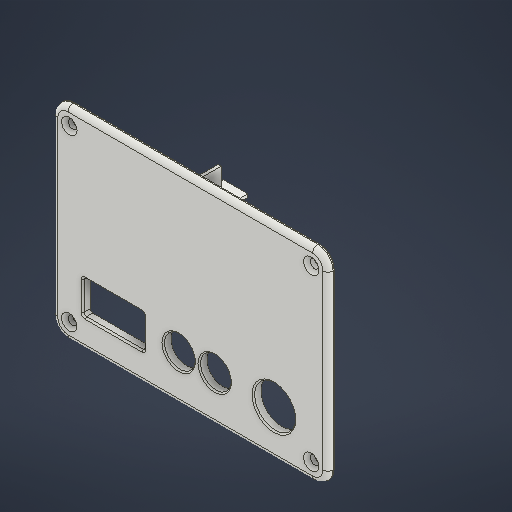
# Autodesk Inventor part: housing_lid
Saved by Autodesk Inventor 2027.1 (Build 311270010, 270A)
## iProperties
Created: 2026-10-22
Part Number: housing_lid
Material: 일반
Document SubType Name: Modeling
Designer: sungjun
Density: 1 g/cm^3
Appearance: housing_lid_c
Author: sungjun
Autodesk Inventor part; units mm, degrees
ref_plane "작업 평면1" through (0, 0, 58) normal (0, 0, 1) x (1, 0, 0)
sketch "스케치1" plane through (0, 0, 58) normal (0, 0, 1) x (1, 0, 0)
  line L0 (0, 0) -> (107, 0)
  line L1 (107, 0) -> (107, 79)
  line L2 (107, 79) -> (0, 79)
  line L3 (0, 79) -> (0, 0)
  constraints: 8 end point, 2 parallel, 1 horizontal, 1 perpendicular
extrude "돌출1" add sketch "스케치1" along normal mid plane 3
fillet "모깎기1" radius 6 4 edges at (0, 0, 58) (0, 79, 58) (107, 79, 58) (107, 0, 58)
fillet "모깎기2" radius 2 8 edges at (105.2426, 1.7574, 59.5) (107, 39.5, 59.5) (105.2426, 77.2426, 59.5) (53.5, 79, 59.5) (1.7574, 77.2426, 59.5) (0, 39.5, 59.5) (1.7574, 1.7574, 59.5) (53.5, 0, 59.5)
chamfer "모따기1" distance 0.6 angle 45 8 edges at (53.5, 79, 56.5) (105.2426, 77.2426, 56.5) (107, 39.5, 56.5) (105.2426, 1.7574, 56.5) (53.5, 0, 56.5) (1.7574, 1.7574, 56.5) (0, 39.5, 56.5) (1.7574, 77.2426, 56.5)
ref_plane "작업 평면2" through (0, 0, 58) normal (0, 0, 1) x (1, 0, 0)
sketch "스케치2" plane through (0, 0, 58) normal (0, 0, 1) x (1, 0, 0)
  circle A0 centre (6.5, 6.5) radius 1.7
  constraints: 1 centre point
extrude "돌출2" cut sketch "스케치2" along normal mid plane 5
ref_plane "작업 평면3" through (0, 0, 58) normal (0, 0, 1) x (1, 0, 0)
sketch "스케치3" plane through (0, 0, 58) normal (0, 0, 1) x (1, 0, 0)
  circle A0 centre (100.5, 6.5) radius 1.7
  constraints: 1 centre point
extrude "돌출3" cut sketch "스케치3" along normal mid plane 5
ref_plane "작업 평면4" through (0, 0, 58) normal (0, 0, 1) x (1, 0, 0)
sketch "스케치4" plane through (0, 0, 58) normal (0, 0, 1) x (1, 0, 0)
  circle A0 centre (6.5, 72.5) radius 1.7
  constraints: 1 centre point
extrude "돌출4" cut sketch "스케치4" along normal mid plane 5
ref_plane "작업 평면5" through (0, 0, 58) normal (0, 0, 1) x (1, 0, 0)
sketch "스케치5" plane through (0, 0, 58) normal (0, 0, 1) x (1, 0, 0)
  circle A0 centre (100.5, 72.5) radius 1.7
  constraints: 1 centre point
extrude "돌출5" cut sketch "스케치5" along normal mid plane 5
chamfer "모따기2" distance 1.3 angle 45 4 edges at (98.8, 72.5, 59.5) (4.8, 72.5, 59.5) (98.8, 6.5, 59.5) (4.8, 6.5, 59.5)
ref_plane "작업 평면6" through (0, 0, 55.5) normal (0, 0, 1) x (1, 0, 0)
sketch "스케치6" plane through (0, 0, 55.5) normal (0, 0, 1) x (1, 0, 0)
  line L0 (3.3, 11) -> (5.3, 11)
  line L1 (5.3, 11) -> (5.3, 68)
  line L2 (5.3, 68) -> (3.3, 68)
  line L3 (3.3, 68) -> (3.3, 11)
  constraints: 8 end point, 2 parallel, 1 horizontal, 1 perpendicular
extrude "돌출6" add sketch "스케치6" along normal mid plane 2
ref_plane "작업 평면7" through (0, 0, 55.5) normal (0, 0, 1) x (1, 0, 0)
sketch "스케치7" plane through (0, 0, 55.5) normal (0, 0, 1) x (1, 0, 0)
  line L0 (101.7, 11) -> (103.7, 11)
  line L1 (103.7, 11) -> (103.7, 68)
  line L2 (103.7, 68) -> (101.7, 68)
  line L3 (101.7, 68) -> (101.7, 11)
  constraints: 8 end point, 2 parallel, 1 horizontal, 1 perpendicular
extrude "돌출7" add sketch "스케치7" along normal mid plane 2
ref_plane "작업 평면8" through (0, 0, 51.6) normal (0, 0, 1) x (1, 0, 0)
sketch "스케치8" plane through (0, 0, 51.6) normal (0, 0, 1) x (1, 0, 0)
  line L0 (51.5, 32.1) -> (52.7, 32.1)
  line L1 (52.7, 32.1) -> (52.7, 75.7)
  line L2 (52.7, 75.7) -> (51.5, 75.7)
  line L3 (51.5, 75.7) -> (51.5, 32.1)
  constraints: 8 end point, 2 parallel, 1 horizontal, 1 perpendicular
extrude "돌출8" add sketch "스케치8" along normal mid plane 9.8
ref_plane "작업 평면9" through (0, 0, 51.6) normal (0, 0, 1) x (1, 0, 0)
sketch "스케치9" plane through (0, 0, 51.6) normal (0, 0, 1) x (1, 0, 0)
  line L0 (24.8, 32.1) -> (52.7, 32.1)
  line L1 (52.7, 32.1) -> (52.7, 33.3)
  line L2 (52.7, 33.3) -> (24.8, 33.3)
  line L3 (24.8, 33.3) -> (24.8, 32.1)
  constraints: 8 end point, 2 parallel, 1 horizontal, 1 perpendicular
extrude "돌출9" add sketch "스케치9" along normal mid plane 9.8
ref_plane "작업 평면10" through (0, 0, 40.55) normal (0, 0, 1) x (1, 0, 0)
sketch "스케치10" plane through (0, 0, 40.55) normal (0, 0, 1) x (1, 0, 0)
  line L0 (3.3, 32.1) -> (15.3, 32.1)
  line L1 (15.3, 32.1) -> (15.3, 33.3)
  line L2 (15.3, 33.3) -> (3.3, 33.3)
  line L3 (3.3, 33.3) -> (3.3, 32.1)
  constraints: 8 end point, 2 parallel, 1 horizontal, 1 perpendicular
extrude "돌출10" add sketch "스케치10" along normal mid plane 31.9
ref_plane "작업 평면11" through (0, 0, 32.45) normal (0, 0, 1) x (1, 0, 0)
sketch "스케치11" plane through (0, 0, 32.45) normal (0, 0, 1) x (1, 0, 0)
  line L0 (15.3, 32.1) -> (24.8, 32.1)
  line L1 (24.8, 32.1) -> (24.8, 33.3)
  line L2 (24.8, 33.3) -> (15.3, 33.3)
  line L3 (15.3, 33.3) -> (15.3, 32.1)
  constraints: 8 end point, 2 parallel, 1 horizontal, 1 perpendicular
extrude "돌출11" add sketch "스케치11" along normal mid plane 48.1
ref_plane "작업 평면12" through (0, 0, 58) normal (0, 0, 1) x (1, 0, 0)
sketch "스케치12" plane through (0, 0, 58) normal (0, 0, 1) x (1, 0, 0)
  line L0 (11.65, 11.15) -> (35.65, 11.15)
  line L1 (35.65, 11.15) -> (35.65, 24.15)
  line L2 (35.65, 24.15) -> (11.65, 24.15)
  line L3 (11.65, 24.15) -> (11.65, 11.15)
  constraints: 8 end point, 2 parallel, 1 horizontal, 1 perpendicular
extrude "돌출12" cut sketch "스케치12" along normal mid plane 5
fillet "모깎기3" radius 1 4 edges at (35.65, 11.15, 58) (35.65, 24.15, 58) (11.65, 24.15, 58) (11.65, 11.15, 58)
chamfer "모따기3" distance 0.6 angle 45 8 edges at (11.9429, 11.4429, 59.5) (23.65, 11.15, 59.5) (11.9429, 23.8571, 59.5) (23.65, 24.15, 59.5) (35.3571, 23.8571, 59.5) (35.65, 17.65, 59.5) (35.3571, 11.4429, 59.5) (11.65, 17.65, 59.5)
ref_plane "작업 평면13" through (0, 0, 58) normal (0, 0, 1) x (1, 0, 0)
sketch "스케치13" plane through (0, 0, 58) normal (0, 0, 1) x (1, 0, 0)
  circle A0 centre (49, 17.65) radius 6
  constraints: 1 centre point
extrude "돌출13" cut sketch "스케치13" along normal mid plane 5
ref_plane "작업 평면14" through (0, 0, 58) normal (0, 0, 1) x (1, 0, 0)
sketch "스케치14" plane through (0, 0, 58) normal (0, 0, 1) x (1, 0, 0)
  circle A0 centre (63, 17.65) radius 6
  constraints: 1 centre point
extrude "돌출14" cut sketch "스케치14" along normal mid plane 5
ref_plane "작업 평면15" through (0, 0, 58) normal (0, 0, 1) x (1, 0, 0)
sketch "스케치15" plane through (0, 0, 58) normal (0, 0, 1) x (1, 0, 0)
  circle A0 centre (86, 17.65) radius 8
  constraints: 1 centre point
extrude "돌출15" cut sketch "스케치15" along normal mid plane 5
chamfer "모따기4" distance 0.5 angle 45 3 edges at (78, 17.65, 59.5) (57, 17.65, 59.5) (43, 17.65, 59.5)
